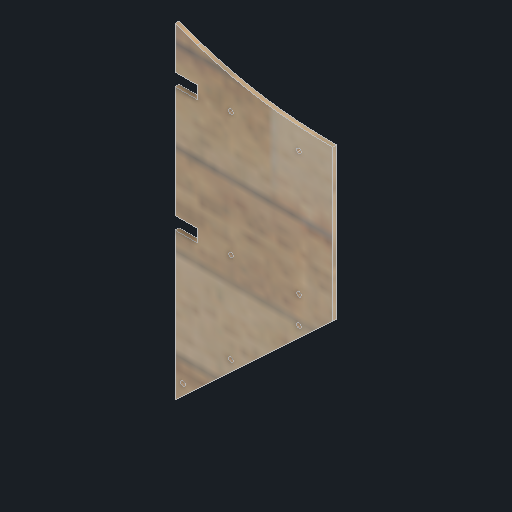
# Autodesk Inventor part: Slope_Left
Saved by Autodesk Inventor 2027.1 (Build 311270010, 270A)
## iProperties
Created: 2026-10-10
Part Number: Slope_Left
Material: 木材 (カエデ材)
Document SubType Name: Modeling
Designer: Takuya Kamada
Density: 0.67 g/cm^3
Appearance: ナチュラル カエデ材 - 光沢 濃い着色
Author: Takuya Kamada
Autodesk Inventor part; units mm, degrees
ref_plane "YZ Plane" through (0, 0, 0) normal (1, 0, 0) x (0, 1, 0)
ref_plane "XZ Plane" through (0, 0, 0) normal (0, 1, 0) x (-1, 0, 0)
ref_plane "XY Plane" through (0, 0, 0) normal (0, 0, 1) x (1, 0, 0)
sketch "スケッチ1" plane through (0, 0, 0) normal (0, 0, 1) x (1, 0, 0)
  line L0 (-85.9977, 0) -> (0, 0) projected
  line L1 (-85.9977, 0) -> (-85.9977, -8) projected
  line L2 (0, -8) -> (-85.9977, -8) projected
  line L3 (0, 0) -> (0, -8) projected
  line L4 (-85.9977, -71.5) -> (0, -71.5) projected
  line L5 (-85.9977, -71.5) -> (-85.9977, -79.5) projected
  line L6 (0, -79.5) -> (-85.9977, -79.5) projected
  line L7 (0, -71.5) -> (0, -79.5) projected
  line L8 (0, 8.7436) -> (-85.9977, 8.7436) construction
  line L9 (-85.9977, 8.7436) -> (-85.9977, -213.7019)
  line L10 (-85.9977, -213.7019) -> (0, -213.7019)
  line L11 (0, -213.7019) -> (0, 8.7436)
  line L12 (-198.4512, 94.8645) -> (-181.391, 74.3945) construction
  line L13 (-181.391, 74.3945) -> (-124.5283, 29.3414) construction
  line L14 (-124.5283, 29.3414) -> (-70.1962, 14.0328) construction
  line L15 (-70.1962, 14.0328) -> (-29.4259, 8.7436) construction
  line L16 (-29.4259, 8.7436) -> (0, 8.7436) construction
  spline S0 degree 4 poles (-198.4512, 94.8645) (-181.391, 74.3945) (-124.5283, 29.3414) (-70.1962, 14.0328) (-29.4259, 8.7436) (0, 8.7436) knots 1 1 1 1 1 2 3 3 3 3 3
  line L17 (-85.9977, 8.7436) -> (-85.9977, 21.8188)
  line L18 (-5.5149, 0) -> (-104.8726, 0) projected
  line L19 (-5.5149, 0) -> (-5.5149, -8) projected
  line L20 (-104.8726, -8) -> (-5.5149, -8) projected
  line L21 (-104.8726, 0) -> (-104.8726, -8) projected
  line L22 (-85.9977, -213.7019) -> (-104.8726, -213.7019)
  line L23 (-104.8726, -213.7019) -> (-104.8726, 28.8877)
  line L24 (-104.8726, 28.8877) -> (-85.9977, 28.8877)
  line L25 (-85.9977, 28.8877) -> (-85.9977, -213.7019)
  circle A0 centre (-64.4983, -75.5) radius 1.5 projected
  circle A1 centre (-21.4994, -75.5) radius 1.5 projected
  circle A2 centre (-64.4983, -4) radius 1.5 projected
  circle A3 centre (-21.4994, -4) radius 1.5 projected
  constraints: 18 end point, 4 parallel, 3 point on line, 2 horizontal, 2 perpendicular, 1 vertical, 6 other
extrude "押し出し1" add sketch "スケッチ1" along normal blind 2.5 contours L9 L17 S0 L11 L0 | L0 L19 L2 L1 | L18 L23 S0 L17 L9 | L0 L3 L2 L19 | L2 L11 L4 L9 | L9 L5 L22 L23 L20 | L4 L7 L6 L5 | L6 L11 L10 L9 | A0 | A1 | A2 | A3
sketch "スケッチ5" plane through (-104.8726, -213.7019, 0) normal (0, -1, 0) x (1, 0, 0)
  line L0 (0, 0) -> (104.8726, 0) projected
  line L1 (104.8726, 0) -> (104.8726, 2.5) projected
  line L2 (0, 2.5) -> (104.8726, 2.5) projected
  line L3 (0, 0) -> (0, 2.5) projected
  line L4 (99.3577, -36.4635) -> (112.3348, -2.8838) projected
  line L5 (112.3348, -2.8838) -> (108.6037, -1.4419) projected
  line L6 (108.6037, -1.4419) -> (109.5049, 0.89) projected
  line L7 (109.5049, 0.89) -> (104.8726, 2.6802) projected
  line L8 (104.8726, 2.6802) -> (104.8726, 0) projected
  line L9 (104.8726, 0) -> (18.875, 0) projected
  line L10 (18.875, 0) -> (18.875, 2.6802) projected
  line L11 (18.875, 2.6802) -> (0.2884, 2.6802) projected
  line L12 (0.2884, 2.6802) -> (0, 1.934) projected
  line L13 (0, 1.934) -> (99.3577, -36.4635) projected
  line L14 (31.813, -5) -> (102.9404, -5) projected
  line L15 (102.9404, -5) -> (93.6979, -28.9158) projected
  line L16 (93.6979, -28.9158) -> (31.813, -5) projected
  line L17 (18.875, 0) -> (0, 0) projected
  line L18 (5.0044, 0) -> (5.0044, 2.5)
  point P0 (5.0044, 0)
  constraints: 3 point on line, 2 end point, 1 perpendicular
extrude "押し出し4" cut sketch "スケッチ5" against normal blind 242 contours L3 L13 L0 | L13 L12 L2 L18 | L3 L2 L12
sketch "スケッチ6" plane through (0, 0, 2.5) normal (0, 0, 1) x (1, 0, 0)
  line L0 (-104.8726, 28.2981) -> (-103.4533, 28.2981) projected
  ellipse E0 centre (-70.9546, 74.4861) end of major axis (43.1011, 35.2621) minor radius 54.7123 (-104.8726, 28.8877) -> (-103.4533, 28.2981) ccw projected
  line L1 (-104.8726, 28.8877) -> (-104.8726, 28.2981) projected
  point P0 (0, 0)
  constraints: 1 other
extrude "押し出し5" cut sketch "スケッチ6" against normal blind 2.5
sketch "スケッチ7" plane through (0, 0, 2.5) normal (0, 0, 1) x (1, 0, 0)
  line L0 (-99.816, -180.654) -> (0.0523, -87.5) projected
  line L1 (-99.8683, 26.8522) -> (-99.8683, 0) projected
  line L2 (-99.8683, 0) -> (-85.9977, 0) projected
  line L3 (-85.9977, 0) -> (-85.9977, -8) projected
  line L4 (-85.9977, -8) -> (-99.8683, -8) projected
  line L5 (-99.8683, -8) -> (-99.8683, -213.7019) projected
  line L6 (-99.8683, -213.7019) -> (0, -213.7019) projected
  line L7 (0, -213.7019) -> (0, 8.7436) projected
  ellipse E0 centre (-70.9546, 74.4861) end of major axis (43.1011, 35.2621) minor radius 54.7123 (-99.8683, 26.8522) -> (-85.9977, 21.8188) ccw projected
  line L8 (0, -86.5915) -> (-99.8683, -179.7455)
  line L9 (-99.8683, -8) -> (-99.8683, -213.7019) projected
  point P0 (0, 0)
  dimension "d13" = 0.7
  constraints: 3 point on line, 2 end point, 1 parallel, 2 other
  measures "d13" distance between parallel lines of L0 L8
extrude "押し出し6" cut sketch "スケッチ7" against normal blind 2.5
sketch "スケッチ8" plane through (0, 0, 2.5) normal (0, 0, 1) x (1, 0, 0)
  circle A0 centre (-64.4983, -4) radius 1.5 projected
  circle A1 centre (-21.4994, -4) radius 1.5 projected
  circle A2 centre (-21.4994, -75.5) radius 1.5 projected
  circle A3 centre (-64.4983, -75.5) radius 1.5 projected
  point P0 (0, 0)
extrude "押し出し7" cut sketch "スケッチ8" against normal blind 2.5 contours A0 | A1
sketch "スケッチ9" plane through (0, 0, 2.5) normal (0, 0, 1) x (1, 0, 0)
  line L0 (-104.5843, -78.5915) -> (-85.9977, -78.5915) projected
  line L1 (-104.5843, -78.5915) -> (-104.5843, -86.5915) projected
  line L2 (-85.9977, -86.5915) -> (-104.5843, -86.5915) projected
  line L3 (-85.9977, -78.5915) -> (-85.9977, -86.5915) projected
  circle A0 centre (-64.4983, -82.5915) radius 1.5 projected
  circle A1 centre (-21.4994, -82.5915) radius 1.5 projected
  point P0 (0, 0)
extrude "押し出し8" cut sketch "スケッチ9" against normal blind 2.5
sketch "スケッチ10" plane through (0, 0, 2.5) normal (0, 0, 1) x (1, 0, 0)
  ellipse E0 centre (256.7744, -176.8913) end of major axis (257.8713, -175.8682) minor radius 1.3051 projected
  ellipse E1 centre (234.2971, -148.5631) end of major axis (235.394, -147.54) minor radius 1.3051 projected
  ellipse E2 centre (202.4729, -108.4552) end of major axis (203.5698, -107.432) minor radius 1.3051 projected
  ellipse E3 centre (-87.5976, -176.8913) end of major axis (-86.5007, -175.8682) minor radius 1.3051 projected
  ellipse E4 centre (-57.2275, -148.5631) end of major axis (-56.1307, -147.54) minor radius 1.3051 projected
  ellipse E5 centre (-14.2287, -108.4552) end of major axis (-13.1318, -107.432) minor radius 1.3051 projected
  line L0 (89.4722, -168.6171) -> (87.6698, -181.5552) projected
  line L1 (16.7793, -181.5552) -> (80.2076, -181.5552) projected
  line L2 (266.8528, -181.5552) -> (192.9387, -88.4012) projected
  line L3 (192.9387, -88.4012) -> (0.8929, -88.4012) projected
  line L4 (0.8929, -88.4012) -> (-98.9754, -181.5552) projected
  line L5 (87.6698, -181.5552) -> (151.0981, -181.5552) projected
  line L6 (80.2076, -181.5552) -> (82.01, -168.6171) projected
  line L7 (82.01, -168.6171) -> (89.4722, -168.6171) projected
  ellipse E6 centre (94.1221, -108.4552) end of major axis (95.219, -107.432) minor radius 1.3051 projected
  ellipse E7 centre (88.5348, -148.5631) end of major axis (89.6316, -147.54) minor radius 1.3051 projected
  line L8 (-85.9977, -86.5915) -> (-99.8683, -86.5915) projected
  line L9 (-99.8683, -86.5915) -> (-99.8683, -179.7455) projected
  line L10 (-99.8683, -179.7455) -> (0, -86.5915) projected
  line L11 (0, -86.5915) -> (0, 8.7436) projected
  ellipse E8 centre (-70.9546, 74.4861) end of major axis (43.1011, 35.2621) minor radius 54.7123 (-99.8683, 26.8522) -> (-85.9977, 21.8188) ccw projected
  line L12 (-99.8683, 26.8522) -> (-99.8683, 0) projected
  line L13 (-99.8683, 0) -> (-85.9977, 0) projected
  line L14 (-85.9977, 0) -> (-85.9977, -8) projected
  line L15 (-85.9977, -8) -> (-99.8683, -8) projected
  line L16 (-99.8683, -8) -> (-99.8683, -78.5915) projected
  line L17 (-99.8683, -78.5915) -> (-85.9977, -78.5915) projected
  line L18 (-85.9977, -78.5915) -> (-85.9977, -86.5915) projected
  circle A0 centre (-21.4994, -82.5915) radius 1.5 projected
  circle A1 centre (-64.4983, -82.5915) radius 1.5 projected
  circle A2 centre (-64.4983, -4) radius 1.5 projected
  circle A3 centre (-21.4994, -4) radius 1.5 projected
  line L19 (5.5091, -108.4552) -> (-28.0982, -108.4552)
  line L20 (0, -79.754) -> (-99.8683, -172.908)
  line L21 (0, -86.5915) -> (0, 8.7436) projected
  line L22 (-21.4994, -4) -> (-21.4994, -99.808)
  circle A4 centre (-21.4994, -99.808) radius 1.5
  line L23 (-64.4983, -4) -> (-64.4983, -139.916)
  circle A5 centre (-64.4983, -139.916) radius 1.5
  circle A6 centre (-94.8683, -168.2442) radius 1.5
  line L24 (18.5817, -168.6171) -> (16.7793, -181.5552) projected
  line L25 (151.0981, -181.5552) -> (152.9004, -168.6171) projected
  line L26 (152.9004, -168.6171) -> (160.3626, -168.6171) projected
  line L27 (160.3626, -168.6171) -> (158.5602, -181.5552) projected
  line L28 (158.5602, -181.5552) -> (266.8528, -181.5552) projected
  line L29 (-98.9754, -181.5552) -> (9.3172, -181.5552) projected
  line L30 (9.3172, -181.5552) -> (11.1196, -168.6171) projected
  line L31 (11.1196, -168.6171) -> (18.5817, -168.6171) projected
  ellipse E9 centre (23.2317, -108.4552) end of major axis (24.3286, -107.432) minor radius 1.3051 projected
  ellipse E10 centre (159.4252, -148.5631) end of major axis (160.5221, -147.54) minor radius 1.3051 projected
  ellipse E11 centre (165.0126, -108.4552) end of major axis (166.1094, -107.432) minor radius 1.3051 projected
  ellipse E12 centre (17.6443, -148.5631) end of major axis (18.7412, -147.54) minor radius 1.3051 projected
  point P0 (0, 0)
  dimension "d20" = 5
  dimension "d21" = 3
  dimension "d22" = 3
  dimension "d23" = 3
  dimension "d24" = 5
  constraints: 8 end point, 6 point on line, 3 centre point, 2 coincident, 1 horizontal, 1 parallel, 1 vertical, 2 other
  measures "d20" distance between parallel lines of L20 L10
  measures "d21" diameter of A4
  measures "d22" diameter of A5
  measures "d23" diameter of A6
  measures "d24" distance from line of L9 A6.centre
extrude "押し出し9" cut sketch "スケッチ10" against normal blind 2.5 contours A6 L20 | L20 A6 | A5 L23 L20 | L20 A5 | L23 A5 L20 | A4 L20 | L20 L22 A4 | L20 A4 L22
